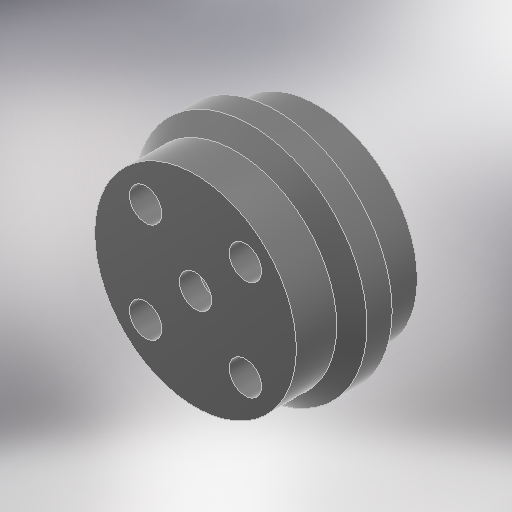
# Autodesk Inventor part: 3D_motor-shaft
Saved by Autodesk Inventor 2025.3 (Build 293356030, 356C)
## iProperties
Created: 2026-05-09
Part Number: 3D_motor-shaft
Material: 一般
Document SubType Name: Modeling
Designer: ibuki_ono
Density: 1 g/cm^3
Appearance: 滑らか - 黒
Author: ibuki_ono
## iProperties of the stored document 3D_motor-shaft_3D プリント.ipt
Created: 2026-05-22
Part Number: 3D_motor-shaft_3D プリント
Material: 一般
Document SubType Name: Modeling
Designer: ibuki_ono
Density: 1 g/cm^3
Appearance: 既定
Author: ibuki_ono
Autodesk Inventor part; units mm, degrees
ref_plane "YZ Plane" through (0, 0, 0) normal (1, 0, 0) x (0, 1, 0)
ref_plane "XZ Plane" through (0, 0, 0) normal (0, 1, 0) x (-1, 0, 0)
ref_plane "XY Plane" through (0, 0, 0) normal (0, 0, 1) x (1, 0, 0)
sketch "スケッチ1" plane through (0, 0, 0) normal (0, 0, 1) x (1, 0, 0)
  circle A0 centre (0, 0) radius 10
  dimension "d0" = 20
  constraints: 1 centre point, 1 coincident
  measures "d0" diameter of A0
extrude "押し出し1" add sketch "スケッチ1" along normal blind 4
sketch "スケッチ2" plane through (0, 0, 4) normal (0, 0, 1) x (1, 0, 0)
  circle A0 centre (0, 0) radius 10 projected
  circle A1 centre (0, 0) radius 11.5
  dimension "d3" = 23
  constraints: 1 centre point, 1 coincident
  measures "d3" diameter of A1
extrude "押し出し2" add sketch "スケッチ2" along normal blind 4 contours A0 | A1
sketch "スケッチ3" plane through (0, 0, 8) normal (0, 0, 1) x (1, 0, 0)
  circle A0 centre (0, 0) radius 10
  dimension "d6" = 20
  constraints: 1 centre point, 1 coincident
  measures "d6" diameter of A0
extrude "押し出し3" add sketch "スケッチ3" along normal blind 4
chamfer "面取り1" distance 1.5 angle 45 1 edges at (-11.5, 0, 8)
sketch "スケッチ4" plane through (0, 0, 0) normal (0, 0, -1) x (-1, 0, 0)
  circle A0 centre (0, 0) radius 7 construction
  line L0 (-4.9497, -4.9497) -> (4.9497, -4.9497) construction
  line L1 (4.9497, -4.9497) -> (4.9497, 4.9497) construction
  line L2 (4.9497, 4.9497) -> (-4.9497, 4.9497) construction
  line L3 (-4.9497, 4.9497) -> (-4.9497, -4.9497) construction
  line L4 (-4.9497, -4.9497) -> (4.9497, 4.9497) construction
  line L5 (4.9497, -4.9497) -> (-4.9497, 4.9497) construction
  dimension "d12" = 14
  constraints: 12 end point, 5 coincident, 2 midpoint, 2 parallel, 2 perpendicular, 1 horizontal, 3 other
hole "穴1" at (4.9497, 4.9497, 0) at (-4.9497, 4.9497, 0) at (-4.9497, -4.9497, 0) at (4.9497, -4.9497, 0) direction (0, 0, 1) diameter 3.2 end through all
sketch "スケッチ5" plane through (0, 0, 0) normal (0, 0, -1) x (-1, 0, 0)
  point P0 (0, 0)
  point P1 (0, 0)
  constraints: 1 coincident
hole "穴2" at (0, 0, 0) direction (0, 0, 1) diameter 3.2 end through all counterbore diameter 7 counterbore depth 10
